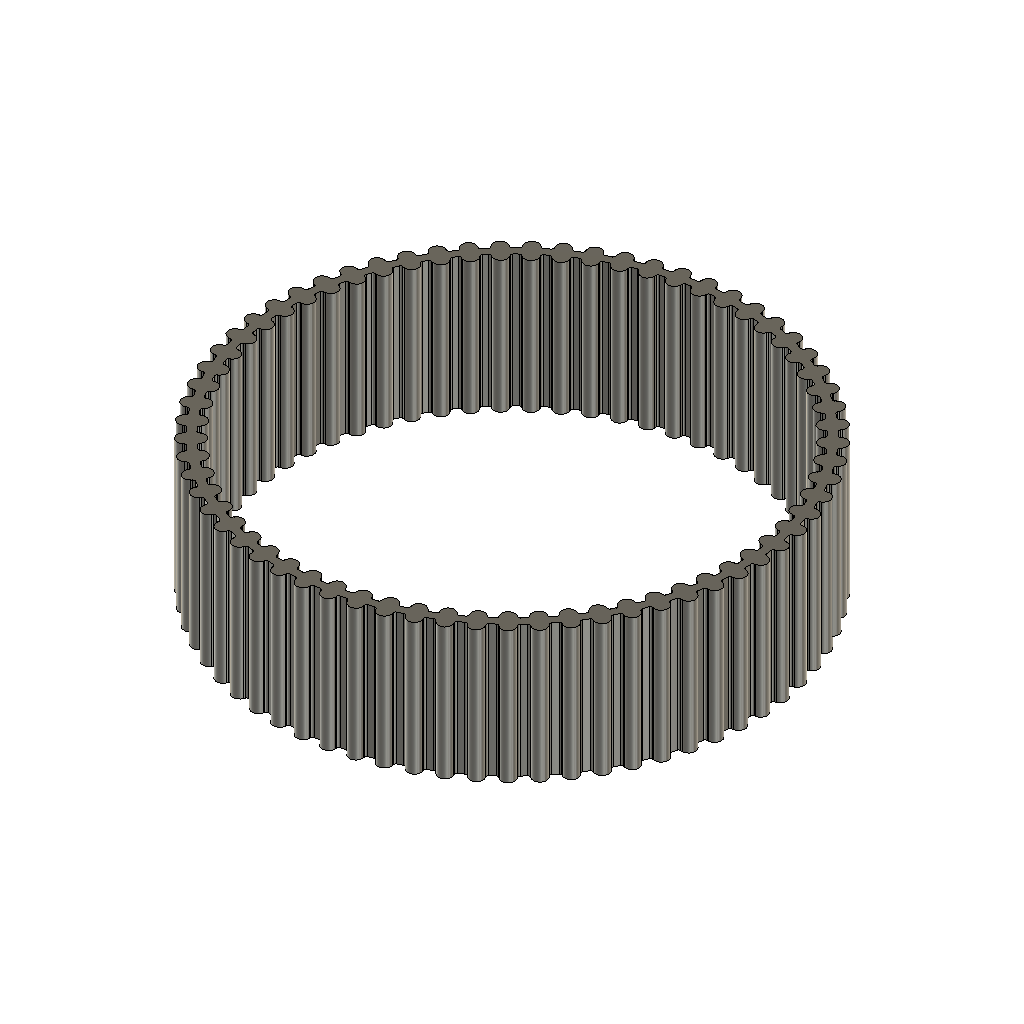
D-HTD-5M Belt Print (Autodesk Fusion 360 design; units mm, degrees)
Autodesk Fusion 360 part; units mm, degrees
sketch "Teeth" plane through (0, 0, 0) normal (0, 0, 1) x (1, 0, 0)
  circle A0 centre (0, 0) radius 51.7254
  arc A1 (0.5018, 50.8529) -> (0, 50.8554) centre (0, 0) ccw
  arc A2 (0.9168, 50.5187) -> (0.5018, 50.8529) centre (0.4976, 50.4229) ccw
  line L0 (0.9168, 50.5187) -> (0.9912, 50.1926)
  arc A3 (0.9912, 50.1926) -> (2.3719, 49.0361) centre (2.4439, 50.5243) ccw
  line L1 (0, 0) -> (0, 50.8554) construction
  line L2 (0, 0) -> (2.4439, 50.5243) construction
  line L3 (0, 50.8554) -> (0, 51.7254)
  arc A4 (2.499, 51.665) -> (0, 51.7254) centre (0, 0) ccw
  arc A5 (2.3719, 49.0361) -> (3.8577, 50.054) centre (2.4439, 50.5243) ccw
  line L4 (3.9632, 50.3713) -> (3.8577, 50.054)
  arc A6 (4.4085, 50.664) -> (3.9632, 50.3713) centre (4.3713, 50.2356) ccw
  arc A7 (4.9083, 50.618) -> (4.4085, 50.664) centre (0, 0) ccw
  line L5 (4.9083, 50.618) -> (4.9922, 51.4839)
  arc A8 (4.9922, 51.4839) -> (2.499, 51.665) centre (0, 0) ccw
  line L6 (0.9168, 50.5187) -> (2.44, 50.445) construction
  line L7 (2.44, 50.445) -> (2.4439, 50.5243) construction
  line L8 (0, 51.7254) -> (0, 52.5954)
  line L9 (1.1054, 53.2558) -> (1.0334, 52.9292)
  arc A9 (0.6085, 52.5919) -> (1.0334, 52.9292) centre (0.6135, 53.0219) ccw
  arc A10 (4.0397, 53.1139) -> (1.1054, 53.2558) centre (2.5605, 52.9349) ccw
  line L10 (4.0397, 53.1139) -> (4.0798, 52.7819)
  arc A11 (4.0798, 52.7819) -> (4.4702, 52.4051) centre (4.5067, 52.8335) ccw
  line L11 (4.9922, 51.4839) -> (5.0762, 52.3499)
  arc A12 (5.0762, 52.3499) -> (4.4702, 52.4051) centre (0, 0) ccw
  arc A13 (0.6085, 52.5919) -> (0, 52.5954) centre (0, 0) ccw
  line L12 (2.44, 50.445) -> (2.5605, 52.9349) construction
  line L13 (1.0334, 52.9292) -> (2.5566, 52.8556) construction
  circle A14 centre (0, 0) radius 50.8554
  dimension "d50" = 103.4508
  dimension "d57" = 0.43
  dimension "d58" = 1.49
  dimension "d59" = 2.769
  dimension "d62" = 2.632
  dimension "d65" = 0.87
  dimension "d67" = 1.525
  dimension "d69" = 0.87
  constraint tangent A1 A2
  constraint coincident A0.centre A1.centre
  constraint vertical A0.centre A1.end
  constraint coincident A0 L3.end
  constraint parallel L1 L3
  constraint coincident A0 A4.start
  constraint collinear A3.centre A0.centre A4.start
  constraint coincident A3.centre L2.end
  constraint coincident L2 A3.end
  constraint symmetric L0.end L2 A5.end
  constraint symmetric A2.start L2 L4.start
  constraint symmetric A1.start L2 A6.start
  constraint symmetric A1 L2 A7
  constraint symmetric A2 L2 A6
  constraint symmetric A3 L2 A5
  constraint symmetric L2 A1.end A7.start
  constraint symmetric L2 L3.end L5.end
  constraint symmetric L2 A4.start A8.end
  constraint symmetric L2 A4 A8
  constraint symmetric L2 A3.end A5.start
  constraint tangent L0 A3
  constraint tangent A2 L0
  constraint perpendicular L2 L6
  constraint parallel L2 L7
  constraint perpendicular A4 L8
  constraint concentric A8 A12
  constraint tangent L9 A9
  constraint tangent L9 A10
  constraint tangent A10 L10
  constraint tangent L10 A11
  constraint perpendicular L11 A12
  constraint tangent A11 A12
  constraint tangent A9 A13
  constraint equal A2 A9
  constraint equal A9 A11
  constraint equal L4 L10
  constraint equal L9 L10
  constraint equal A3 A10
  constraint concentric A12 A13
  constraint coincident A10.centre L12.end
  constraint perpendicular A0 L12
  constraint equal L8 L11
  constraint coincident L12 L13.end
  constraint perpendicular L12 L13
  constraint equal L6 L13
  constraint concentric A4 A14
  constraint coincident A1.end A14
  measures "d50" diameter of A0
  measures "d57" radius of A2
  measures "d58" radius of A3
  measures "d59" angle of L1 L2
  measures "d62" distance of A4.start A3.end
  measures "d65" distance of A1.end L3.end
  measures "d67" distance of A2.start L6.end
  measures "d69" distance of L3.end L8.end
extrude "Extrude4" add sketch "Teeth" along normal blind 15 contours A0 L3 L5 A14 | A0 A1 L3 A4 A7 L5 A8 A14
extrude "Extrude3" add sketch "Teeth" along normal mid plane 30 contours A0 A1 L3 A4 A7 L5 A8 A14 | A0 A4 A8 L8 L9 A9 A10 L10 A11 L11 A12 A13 | A2 L0 A3 A5 L4 A6 A14
pattern_circular "C-Pattern1" count 65 over 360 about axis through (0, 0, 0) along (0, 0, 1) of "Extrude3"
equation "p = 5 mm"
equation "n = 65" comment "Number of Teeth"
equation "PD = n * p / 3.14159"
equation "d50 = PD"
equation "d52 = n"
equation "d59 = ( 180 / n ) * 1 deg"
equation "width = 15 mm"
equation "d67 = 3.05 mm / 2"
equation "d69 = d65"
equation "d70 = width"
equation "d71 = width"
